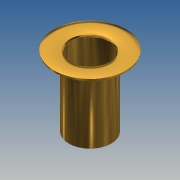
# Autodesk Inventor part: S45 ONYX STANDARD METAL GEAR SERVO (EYELET)
Saved by Autodesk Inventor 2022.1 (Build 261234000, 234)
## iProperties
Created: 2021-08-13
Part Number: S45 ONYX STANDARD METAL GEAR SERVO (EYELET)
Material: Brass, Soft Yellow
Document SubType Name: Modeling
Designer: dotwibo2
Density: 8.47 g/cm^3
Appearance: Brass - Satin
Mass: 0.0794803 g
Surface Area: 1.14468 cm^2
Volume: 0.00938375 cm^3
Author: dotwibo2
Autodesk Inventor part; units mm, degrees
ref_plane "YZ Plane" through (0, 0, 0) normal (1, 0, 0) x (0, 1, 0)
ref_plane "XZ Plane" through (0, 0, 0) normal (0, 1, 0) x (-1, 0, 0)
ref_plane "XY Plane" through (0, 0, 0) normal (0, 0, 1) x (1, 0, 0)
sketch "Sketch1" plane through (0, 0, 0) normal (0, 0, 1) x (1, 0, 0)
  line L0 (-1.1008, 0) -> (6.6049, 0) construction
  line L1 (0, -6.0025) -> (0, 1.0153) projected
  line L2 (1.305, -5) -> (1.305, -0.2598)
  arc A0 (2.5, -0.0729) -> (1.4185, -0.0994) centre (2, -1.75) ccw
  line L3 (1.475, -5) -> (1.475, -0.2598)
  arc A1 (2.4514, -0.2359) -> (1.475, -0.2598) centre (2, -1.75) ccw
  line L4 (2.4514, -0.2359) -> (2.5, -0.0729)
  line L5 (0.3561, 0) -> (5.504, 0) construction
  line L6 (1.305, -5) -> (1.475, -5)
  arc A2 (1.4185, -0.0994) -> (1.305, -0.2598) centre (1.475, -0.2598) ccw
  point P0 (0, 0)
  dimension "d0" = 2.61
  dimension "d2" = 0.17
  dimension "d3" = 5
  dimension "d4" = 1.75
  dimension "d5" = 4
  dimension "d6" = 5
  constraints: 10 end point, 6 point on circle, 3 centre point, 3 tangent, 2 horizontal, 1 coincident, 1 collinear, 1 point on line, 1 vertical, 1 other
  measures "d0" diameter of L2 L1
  measures "d2" distance between parallel lines of L3 L2
  measures "d3" diameter of L4.end L1
  measures "d4" radius of A0
  measures "d5" diameter of A0.centre L1
  measures "d6" distance between parallel lines of L5 L6
revolve "Revolution1" add sketch "Sketch1" angle 360 about axis through (0, -10, 0) along (0, 1, 0)
body "Solid1"
